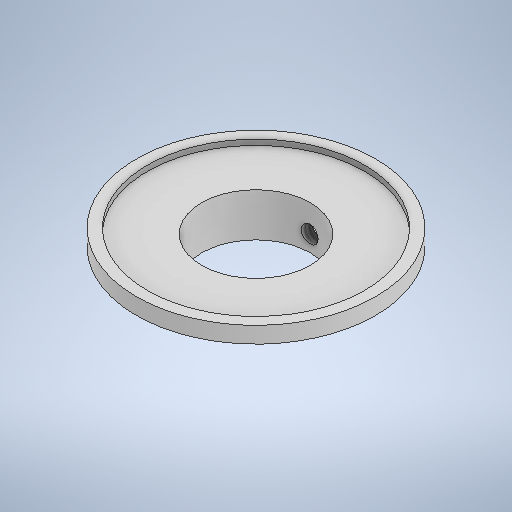
# Autodesk Inventor part: sprzeglo_przód
Saved by Autodesk Inventor 2025.2 (Build 292293000, 293)
## iProperties
Created: 2025-04-06
Part Number: sprzeglo_przód
Material: Ogólny
Document SubType Name: Modeling
Designer: Jan Bołtralik
Density: 1 g/cm^3
Appearance: Domyślna
Author: Jan Bołtralik
Autodesk Inventor part; units mm, degrees
ref_plane "YZ Plane" through (0, 0, 0) normal (1, 0, 0) x (0, 1, 0)
ref_plane "XZ Plane" through (0, 0, 0) normal (0, 1, 0) x (-1, 0, 0)
ref_plane "XY Plane" through (0, 0, 0) normal (0, 0, 1) x (1, 0, 0)
sketch "Szkic1" plane through (0, 0, 0) normal (0, 0, 1) x (1, 0, 0)
  line L0 (0, 0) -> (0, 10)
  line L1 (5, 0) -> (5, 4)
  line L2 (5, 4) -> (10, 4)
  line L3 (10, 4) -> (10, 4.5)
  line L4 (10, 4.5) -> (11, 4.5)
  line L5 (11, 4.5) -> (11, 3)
  line L6 (11, 3) -> (6, 3)
  line L7 (6, 3) -> (6, 0)
  line L8 (6, 0) -> (5, 0)
  point P0 (11, 3.75)
  dimension "d0" = 10
  dimension "d2" = 4
  dimension "d3" = 10
  dimension "d4" = 12
  dimension "d5" = 20
  dimension "d6" = 22
  dimension "d7" = 3
  dimension "d8" = 0.5
  constraints: 18 end point, 6 perpendicular, 3 vertical, 2 horizontal, 1 midpoint
  measures "d0" distance of L0.start L0.end
  measures "d2" distance of L1.start L1.end
  measures "d3" diameter of L1 L0
  measures "d4" diameter of L7 L0
  measures "d5" diameter of L3 L0
  measures "d6" diameter of point (11, 3.75) L0
  measures "d7" distance of L6.end L7.end
  measures "d8" distance of L2.end L3.end
revolve "Obrót1" add sketch "Szkic1" angle 360 about axis through (0, 0, 0) along (0, 1, 0)
sketch "Sketch2" plane through (0, 0, 0) normal (0, 0, 1) x (1, 0, 0)
  line L0 (-6, 0) -> (-6, 3) projected
  line L1 (6, 0) -> (-6, 0) projected
  line L2 (6, 0) -> (6, 3) projected
  point P0 (0, 0)
  point P1 (0, 1.5)
  dimension "d10" = 1.5
  measures "d10" distance from line of L1 point (0, 1.5)
hole "Hole1" at (0, 1.5, 0) direction (0, 0, -1) diameter 1.567 end through all thread size "M2x0.4" class "6H" standard "ISO Metric profile"
